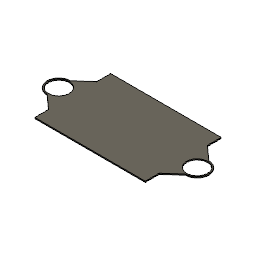
casing (Autodesk Fusion 360 archive; units mm, degrees)
design "lidar"
part number: 2026-07-04-18-04-53-543
Autodesk Fusion 360 part; units mm, degrees
sketch "Sketch1" plane through (0, 0, 0) normal (0, 0, 1) x (1, 0, 0)
  line L0 (8, 5.5) -> (-8, 5.5)
  line L1 (-8, 5.5) -> (-8, -5.5)
  line L2 (-8, -5.5) -> (8, -5.5)
  line L3 (8, -5.5) -> (8, 5.5)
  line L4 (8, 5.5) -> (-8, -5.5) construction
  line L5 (-8, 5.5) -> (8, -5.5) construction
  circle A0 centre (10, 0) radius 1.5
  circle A1 centre (10, 0) radius 1.5
  circle A2 centre (10, 0) radius 1.5
  line L6 (8, -5.5) -> (8, -3.5)
  line L7 (8, 5.5) -> (8, 3.5)
  circle A3 centre (10, 0) radius 1.7
  line L8 (8, -3.5) -> (10, -1.7)
  line L9 (8, 3.5) -> (10, 1.7)
  line L10 (0, 2.5) -> (0, 20)
  line L11 (-8, -3.5) -> (-10, -1.7)
  circle A4 centre (-10, 0) radius 1.7
  circle A5 centre (-10, 0) radius 1.5
  line L12 (-8, 3.5) -> (-10, 1.7)
  dimension "d1" = 16
  dimension "d2" = 11
  dimension "d3" = 3
  dimension "d4" = 3
  dimension "d5" = 3
  dimension "d8" = 2
  dimension "d10" = 2
  dimension "d11" = 2
  dimension "d12" = 0.2
  constraint horizontal L0
  constraint perpendicular L0 L1
  constraint parallel L0 L2
  constraint parallel L1 L3
  constraint coincident L4 origin
  constraint coincident L5 origin
  constraint perpendicular L2 L6
  constraint perpendicular L0 L7
  constraint coincident A3 L8.end
  constraint coincident A3 L9.end
  constraint symmetric A2 L10 A5
  constraint symmetric L6.end L10 L11.start
  constraint symmetric L7.end L10 L12.start
  constraint symmetric A3 L10 A4
  constraint symmetric L8.end L10 L11.end
  constraint symmetric L9.end L10 L12.end
  measures "d1" distance of L1.end L2.end
  measures "d2" distance of L0.end L1.end
  measures "d3" diameter of A0
  measures "d4" diameter of A1
  measures "d5" diameter of A2
  measures "d8" distance of L3 A0.centre
  measures "d10" distance of L2.end L6.end
  measures "d11" distance of L0.start L7.end
extrude "Extrude1" add sketch "Sketch1" along normal blind 0.15
